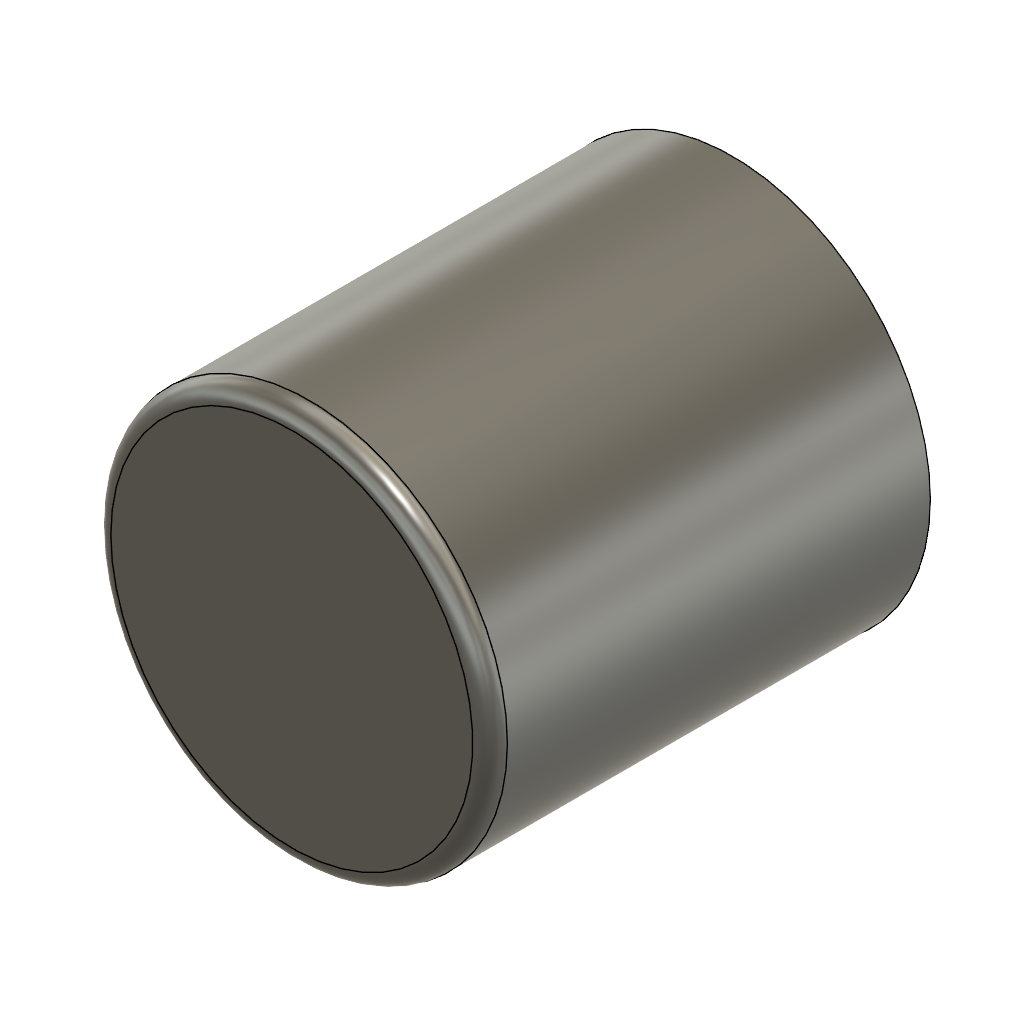
Native (Autodesk Fusion 360 design; units mm, degrees)
part number: 2026-11-25-22-52-36-592
Autodesk Fusion 360 part; units mm, degrees
sketch "Disc sketch" plane through (0, 0, 0) normal (0, 0, 1) x (1, 0, 0)
  circle A0 centre (0, 0) radius 14.9
extrude "Disc extrude" add sketch "Disc sketch" along normal blind 33.1
fillet "Rim round" radius 1.3 1 edges at (-13.8917, -5.3881, 33.1)
